Autodesk Fusion 360 part; units mm, degrees
(part 7 of 7)
  spline S31 degree 5 poles (-13.4039, -14.1628) (-13.3959, -14.1604) (-13.3799, -14.1556) (-13.356, -14.1483) (-13.3241, -14.1385) (-13.2844, -14.1261) (-13.2448, -14.1135) (-13.2053, -14.1007) (-13.1659, -14.0879) (-13.1266, -14.0748) (-13.0874, -14.0616) (-13.0484, -14.0482) (-13.0094, -14.0347) (-12.9706, -14.021) (-12.9319, -14.0072) (-12.8933, -13.9932) (-12.8548, -13.979) (-12.8164, -13.9647) (-12.7782, -13.9502) (-12.7401, -13.9355) (-12.7021, -13.9207) (-12.6642, -13.9057) (-12.6265, -13.8905) (-12.5889, -13.8752) (-12.5514, -13.8597) (-12.5141, -13.844) (-12.4768, -13.8282) (-12.4398, -13.8122) (-12.4028, -13.796) (-12.366, -13.7797) (-12.3294, -13.7632) (-12.2928, -13.7465) (-12.2565, -13.7296) (-12.2202, -13.7126) (-12.1842, -13.6954) (-12.1482, -13.678) (-12.1124, -13.6604) (-12.0768, -13.6426) (-12.0413, -13.6247) (-12.006, -13.6066) (-11.9709, -13.5883) (-11.9359, -13.5698) (-11.9011, -13.5511) (-11.8664, -13.5322) (-11.832, -13.5131) (-11.7977, -13.4939) (-11.7636, -13.4744) (-11.7296, -13.4547) (-11.6959, -13.4349) (-11.6623, -13.4148) (-11.6289, -13.3946) (-11.5958, -13.3741) (-11.5628, -13.3533) (-11.5301, -13.3324) (-11.4976, -13.3112) (-11.4653, -13.2898) (-11.4332, -13.2682) (-11.4013, -13.2464) (-11.3696, -13.2244) (-11.3382, -13.2021) (-11.307, -13.1795) (-11.2762, -13.1566) (-11.2458, -13.1334) (-11.2157, -13.1098) (-11.186, -13.0858) (-11.1564, -13.0617) (-11.1271, -13.0374) (-11.098, -13.0129) (-11.0691, -12.9882) (-11.0407, -12.963) (-11.0131, -12.9371) (-10.9919, -12.9156) (-10.9766, -12.8989) (-10.9666, -12.8875) (-10.9617, -12.8818) knots -1 -1 -1 -1 -1 -1 -0.98571429 -0.97142857 -0.95714286 -0.94285714 -0.92857143 -0.91428571 -0.9 -0.88571429 -0.87142857 -0.85714286 -0.84285714 -0.82857143 -0.81428571 -0.8 -0.78571429 -0.77142857 -0.75714286 -0.74285714 -0.72857143 -0.71428571 -0.7 -0.68571429 -0.67142857 -0.65714286 -0.64285714 -0.62857143 -0.61428571 -0.6 -0.58571429 -0.57142857 -0.55714286 -0.54285714 -0.52857143 -0.51428571 -0.5 -0.48571429 -0.47142857 -0.45714286 -0.44285714 -0.42857143 -0.41428571 -0.4 -0.38571429 -0.37142857 -0.35714286 -0.34285714 -0.32857143 -0.31428571 -0.3 -0.28571429 -0.27142857 -0.25714286 -0.24285714 -0.22857143 -0.21428571 -0.2 -0.18571429 -0.17142857 -0.15714286 -0.14285714 -0.12857143 -0.11428571 -0.1 -0.08571429 -0.07142857 -0.05714286 -0.04285714 -0.02857143 -0.01428571 0 0 0 0 0 0
  line L31 (-10.9617, -12.8818) -> (-10.8597, -12.7619)
  arc A63 (-10.1664, -12.6956) -> (-10.8597, -12.7619) centre (-10.4789, -13.0859) ccw
  arc A64 (-10.1664, -12.6956) -> (-9.6318, -13.1058) centre (0, 0) ccw
  arc A65 (-9.5163, -13.7927) -> (-9.6318, -13.1058) centre (-9.9279, -13.5087) ccw
  line L32 (-9.5163, -13.7927) -> (-9.6057, -13.9222)
  spline S32 degree 5 poles (-9.6057, -13.9222) (-9.61, -13.9285) (-9.6185, -13.941) (-9.6306, -13.9602) (-9.6459, -13.9862) (-9.6638, -14.0196) (-9.6807, -14.0535) (-9.6971, -14.0878) (-9.7132, -14.1223) (-9.7291, -14.1569) (-9.7448, -14.1917) (-9.7602, -14.2266) (-9.7752, -14.2618) (-9.7898, -14.2972) (-9.804, -14.3329) (-9.8177, -14.3688) (-9.8311, -14.4049) (-9.8441, -14.4412) (-9.8569, -14.4777) (-9.8695, -14.5143) (-9.8818, -14.551) (-9.8939, -14.5879) (-9.9057, -14.6249) (-9.9171, -14.6621) (-9.9284, -14.6994) (-9.9393, -14.7369) (-9.95, -14.7745) (-9.9604, -14.8123) (-9.9706, -14.8502) (-9.9806, -14.8882) (-9.9903, -14.9263) (-9.9998, -14.9645) (-10.0091, -15.0028) (-10.0182, -15.0413) (-10.027, -15.0799) (-10.0356, -15.1186) (-10.0439, -15.1574) (-10.0521, -15.1963) (-10.06, -15.2353) (-10.0677, -15.2744) (-10.0752, -15.3136) (-10.0825, -15.3529) (-10.0896, -15.3923) (-10.0965, -15.4318) (-10.1031, -15.4714) (-10.1096, -15.5111) (-10.1159, -15.5509) (-10.1219, -15.5908) (-10.1278, -15.6307) (-10.1334, -15.6708) (-10.1389, -15.7109) (-10.1442, -15.7511) (-10.1492, -15.7914) (-10.1541, -15.8318) (-10.1588, -15.8722) (-10.1633, -15.9127) (-10.1676, -15.9533) (-10.1717, -15.994) (-10.1756, -16.0348) (-10.1793, -16.0756) (-10.1829, -16.1165) (-10.1862, -16.1575) (-10.1894, -16.1986) (-10.1924, -16.2397) (-10.1952, -16.2809) (-10.1978, -16.3221) (-10.2002, -16.3635) (-10.2025, -16.4049) (-10.2046, -16.4463) (-10.2065, -16.4878) (-10.2082, -16.5294) (-10.2094, -16.5627) (-10.2102, -16.5878) (-10.2108, -16.6045) (-10.211, -16.6128) knots 0 0 0 0 0 0 0.01428571 0.02857143 0.04285714 0.05714286 0.07142857 0.08571429 0.1 0.11428571 0.12857143 0.14285714 0.15714286 0.17142857 0.18571429 0.2 0.21428571 0.22857143 0.24285714 0.25714286 0.27142857 0.28571429 0.3 0.31428571 0.32857143 0.34285714 0.35714286 0.37142857 0.38571429 0.4 0.41428571 0.42857143 0.44285714 0.45714286 0.47142857 0.48571429 0.5 0.51428571 0.52857143 0.54285714 0.55714286 0.57142857 0.58571429 0.6 0.61428571 0.62857143 0.64285714 0.65714286 0.67142857 0.68571429 0.7 0.71428571 0.72857143 0.74285714 0.75714286 0.77142857 0.78571429 0.8 0.81428571 0.82857143 0.84285714 0.85714286 0.87142857 0.88571429 0.9 0.91428571 0.92857143 0.94285714 0.95714286 0.97142857 0.98571429 1 1 1 1 1 1
  arc A66 (-10.211, -16.6128) -> (-9.2816, -17.1494) centre (0, 0) ccw
  spline S33 degree 5 poles (-9.2816, -17.1494) (-9.2745, -17.145) (-9.2603, -17.1362) (-9.2391, -17.123) (-9.2108, -17.1053) (-9.1757, -17.083) (-9.1406, -17.0606) (-9.1058, -17.0381) (-9.0711, -17.0154) (-9.0365, -16.9926) (-9.0021, -16.9697) (-8.9678, -16.9467) (-8.9337, -16.9236) (-8.8997, -16.9003) (-8.8659, -16.8769) (-8.8322, -16.8534) (-8.7987, -16.8297) (-8.7654, -16.806) (-8.7322, -16.7821) (-8.6992, -16.758) (-8.6663, -16.7339) (-8.6336, -16.7096) (-8.6011, -16.6852) (-8.5688, -16.6606) (-8.5366, -16.636) (-8.5045, -16.6112) (-8.4727, -16.5863) (-8.441, -16.5612) (-8.4095, -16.536) (-8.3782, -16.5107) (-8.3471, -16.4853) (-8.3161, -16.4597) (-8.2853, -16.434) (-8.2548, -16.4082) (-8.2244, -16.3822) (-8.1942, -16.3561) (-8.1642, -16.3299) (-8.1343, -16.3035) (-8.1047, -16.277) (-8.0753, -16.2503) (-8.0461, -16.2236) (-8.0171, -16.1966) (-7.9883, -16.1696) (-7.9597, -16.1424) (-7.9314, -16.115) (-7.9032, -16.0875) (-7.8753, -16.0599) (-7.8476, -16.0321) (-7.8201, -16.0042) (-7.7929, -15.9762) (-7.7659, -15.9479) (-7.7392, -15.9196) (-7.7127, -15.891) (-7.6866, -15.8623) (-7.6606, -15.8334) (-7.635, -15.8044) (-7.6096, -15.7752) (-7.5844, -15.7459) (-7.5595, -15.7164) (-7.5349, -15.6868) (-7.5106, -15.6569) (-7.4868, -15.6268) (-7.4634, -15.5965) (-7.4405, -15.5659) (-7.4179, -15.5351) (-7.3957, -15.5041) (-7.3736, -15.4731) (-7.3518, -15.4419) (-7.3303, -15.4105) (-7.3094, -15.3789) (-7.2895, -15.3467) (-7.2745, -15.3204) (-7.2641, -15.3003) (-7.2574, -15.2868) (-7.2542, -15.2799) knots -1 -1 -1 -1 -1 -1 -0.98571429 -0.97142857 -0.95714286 -0.94285714 -0.92857143 -0.91428571 -0.9 -0.88571429 -0.87142857 -0.85714286 -0.84285714 -0.82857143 -0.81428571 -0.8 -0.78571429 -0.77142857 -0.75714286 -0.74285714 -0.72857143 -0.71428571 -0.7 -0.68571429 -0.67142857 -0.65714286 -0.64285714 -0.62857143 -0.61428571 -0.6 -0.58571429 -0.57142857 -0.55714286 -0.54285714 -0.52857143 -0.51428571 -0.5 -0.48571429 -0.47142857 -0.45714286 -0.44285714 -0.42857143 -0.41428571 -0.4 -0.38571429 -0.37142857 -0.35714286 -0.34285714 -0.32857143 -0.31428571 -0.3 -0.28571429 -0.27142857 -0.25714286 -0.24285714 -0.22857143 -0.21428571 -0.2 -0.18571429 -0.17142857 -0.15714286 -0.14285714 -0.12857143 -0.11428571 -0.1 -0.08571429 -0.07142857 -0.05714286 -0.04285714 -0.02857143 -0.01428571 0 0 0 0 0 0
  line L33 (-7.2542, -15.2799) -> (-7.1866, -15.1377)
  arc A67 (-6.5341, -14.8943) -> (-7.1866, -15.1377) centre (-6.735, -15.3522) ccw
  arc A68 (-6.5341, -14.8943) -> (-5.9116, -15.1521) centre (0, 0) ccw
  arc A69 (-5.6223, -15.7857) -> (-5.9116, -15.1521) centre (-6.0933, -15.6179) ccw
  line L34 (-5.6223, -15.7857) -> (-5.6751, -15.934)
  spline S34 degree 5 poles (-5.6751, -15.934) (-5.6776, -15.9411) (-5.6825, -15.9554) (-5.6893, -15.9771) (-5.6973, -16.0062) (-5.706, -16.043) (-5.7136, -16.0802) (-5.7205, -16.1176) (-5.7271, -16.1551) (-5.7335, -16.1926) (-5.7397, -16.2302) (-5.7455, -16.268) (-5.7509, -16.3058) (-5.7559, -16.3438) (-5.7603, -16.3819) (-5.7643, -16.4202) (-5.7678, -16.4586) (-5.771, -16.497) (-5.774, -16.5355) (-5.7766, -16.5741) (-5.779, -16.6128) (-5.7811, -16.6515) (-5.7829, -16.6904) (-5.7844, -16.7293) (-5.7856, -16.7682) (-5.7864, -16.8073) (-5.787, -16.8464) (-5.7873, -16.8855) (-5.7874, -16.9247) (-5.7872, -16.964) (-5.7867, -17.0034) (-5.786, -17.0427) (-5.785, -17.0822) (-5.7838, -17.1217) (-5.7824, -17.1612) (-5.7806, -17.2008) (-5.7787, -17.2405) (-5.7765, -17.2802) (-5.774, -17.3199) (-5.7714, -17.3597) (-5.7685, -17.3995) (-5.7653, -17.4393) (-5.762, -17.4792) (-5.7584, -17.5192) (-5.7546, -17.5591) (-5.7506, -17.5991) (-5.7463, -17.6392) (-5.7418, -17.6793) (-5.7372, -17.7194) (-5.7323, -17.7595) (-5.7272, -17.7997) (-5.7218, -17.8399) (-5.7163, -17.8801) (-5.7106, -17.9204) (-5.7046, -17.9607) (-5.6985, -18.001) (-5.6921, -18.0413) (-5.6855, -18.0817) (-5.6788, -18.1221) (-5.6718, -18.1625) (-5.6646, -18.2029) (-5.6573, -18.2434) (-5.6497, -18.2838) (-5.6419, -18.3243) (-5.634, -18.3648) (-5.6258, -18.4054) (-5.6175, -18.4459) (-5.609, -18.4865) (-5.6002, -18.5271) (-5.5913, -18.5677) (-5.5822, -18.6083) (-5.5748, -18.6408) (-5.5691, -18.6652) (-5.5653, -18.6814) (-5.5634, -18.6895) knots 0 0 0 0 0 0 0.01428571 0.02857143 0.04285714 0.05714286 0.07142857 0.08571429 0.1 0.11428571 0.12857143 0.14285714 0.15714286 0.17142857 0.18571429 0.2 0.21428571 0.22857143 0.24285714 0.25714286 0.27142857 0.28571429 0.3 0.31428571 0.32857143 0.34285714 0.35714286 0.37142857 0.38571429 0.4 0.41428571 0.42857143 0.44285714 0.45714286 0.47142857 0.48571429 0.5 0.51428571 0.52857143 0.54285714 0.55714286 0.57142857 0.58571429 0.6 0.61428571 0.62857143 0.64285714 0.65714286 0.67142857 0.68571429 0.7 0.71428571 0.72857143 0.74285714 0.75714286 0.77142857 0.78571429 0.8 0.81428571 0.82857143 0.84285714 0.85714286 0.87142857 0.88571429 0.9 0.91428571 0.92857143 0.94285714 0.95714286 0.97142857 0.98571429 1 1 1 1 1 1
  arc A70 (-5.5634, -18.6895) -> (-4.5267, -18.9673) centre (0, 0) ccw
  spline S35 degree 5 poles (-4.5267, -18.9673) (-4.521, -18.9612) (-4.5096, -18.949) (-4.4925, -18.9308) (-4.4698, -18.9063) (-4.4416, -18.8757) (-4.4136, -18.845) (-4.3857, -18.8142) (-4.3581, -18.7834) (-4.3306, -18.7524) (-4.3032, -18.7214) (-4.2761, -18.6903) (-4.2491, -18.6591) (-4.2223, -18.6278) (-4.1957, -18.5965) (-4.1693, -18.5651) (-4.1431, -18.5336) (-4.117, -18.502) (-4.0912, -18.4703) (-4.0655, -18.4385) (-4.04, -18.4067) (-4.0147, -18.3748) (-3.9896, -18.3428) (-3.9647, -18.3107) (-3.94, -18.2786) (-3.9155, -18.2463) (-3.8912, -18.214) (-3.867, -18.1816) (-3.8431, -18.1491) (-3.8194, -18.1166) (-3.7959, -18.0839) (-3.7727, -18.0512) (-3.7496, -18.0184) (-3.7267, -17.9856) (-3.7041, -17.9526) (-3.6817, -17.9196) (-3.6595, -17.8865) (-3.6375, -17.8533) (-3.6158, -17.82) (-3.5942, -17.7867) (-3.573, -17.7532) (-3.5519, -17.7197) (-3.5311, -17.6861) (-3.5105, -17.6525) (-3.4902, -17.6187) (-3.4702, -17.5849) (-3.4504, -17.551) (-3.4308, -17.517) (-3.4115, -17.4829) (-3.3924, -17.4487) (-3.3737, -17.4145) (-3.3552, -17.3802) (-3.337, -17.3457) (-3.3192, -17.3112) (-3.3016, -17.2766) (-3.2844, -17.2419) (-3.2674, -17.2072) (-3.2506, -17.1724) (-3.2342, -17.1374) (-3.2181, -17.1024) (-3.2024, -17.0673) (-3.1872, -17.0321) (-3.1724, -16.9967) (-3.1582, -16.9612) (-3.1444, -16.9257) (-3.1309, -16.89) (-3.1177, -16.8543) (-3.1047, -16.8185) (-3.092, -16.7827) (-3.08, -16.7467) (-3.0691, -16.7104) (-3.0614, -16.6812) (-3.0565, -16.6591) (-3.0536, -16.6442) (-3.0522, -16.6368) knots -1 -1 -1 -1 -1 -1 -0.98571429 -0.97142857 -0.95714286 -0.94285714 -0.92857143 -0.91428571 -0.9 -0.88571429 -0.87142857 -0.85714286 -0.84285714 -0.82857143 -0.81428571 -0.8 -0.78571429 -0.77142857 -0.75714286 -0.74285714 -0.72857143 -0.71428571 -0.7 -0.68571429 -0.67142857 -0.65714286 -0.64285714 -0.62857143 -0.61428571 -0.6 -0.58571429 -0.57142857 -0.55714286 -0.54285714 -0.52857143 -0.51428571 -0.5 -0.48571429 -0.47142857 -0.45714286 -0.44285714 -0.42857143 -0.41428571 -0.4 -0.38571429 -0.37142857 -0.35714286 -0.34285714 -0.32857143 -0.31428571 -0.3 -0.28571429 -0.27142857 -0.25714286 -0.24285714 -0.22857143 -0.21428571 -0.2 -0.18571429 -0.17142857 -0.15714286 -0.14285714 -0.12857143 -0.11428571 -0.1 -0.08571429 -0.07142857 -0.05714286 -0.04285714 -0.02857143 -0.01428571 0 0 0 0 0 0
  line L35 (-3.0522, -16.6368) -> (-3.0238, -16.482)
  arc A71 (-2.4565, -16.0779) -> (-3.0238, -16.482) centre (-2.532, -16.5722) ccw
  arc A72 (-2.4565, -16.0779) -> (-1.7885, -16.1659) centre (0, 0) ccw
  arc A73 (-1.3451, -16.703) -> (-1.7885, -16.1659) centre (-1.8434, -16.6628) ccw
  line L36 (-1.3451, -16.703) -> (-1.3577, -16.8599)
  spline S36 degree 5 poles (-1.3577, -16.8599) (-1.3583, -16.8674) (-1.3593, -16.8825) (-1.3603, -16.9052) (-1.3605, -16.9354) (-1.3593, -16.9732) (-1.357, -17.0111) (-1.3541, -17.049) (-1.3508, -17.0869) (-1.3472, -17.1248) (-1.3434, -17.1628) (-1.3393, -17.2007) (-1.3347, -17.2387) (-1.3297, -17.2766) (-1.3241, -17.3146) (-1.318, -17.3526) (-1.3115, -17.3906) (-1.3047, -17.4285) (-1.2975, -17.4665) (-1.2901, -17.5045) (-1.2824, -17.5425) (-1.2744, -17.5804) (-1.2661, -17.6184) (-1.2574, -17.6563) (-1.2485, -17.6943) (-1.2392, -17.7322) (-1.2297, -17.7701) (-1.2198, -17.808) (-1.2097, -17.8459) (-1.1994, -17.8838) (-1.1888, -17.9217) (-1.1779, -17.9596) (-1.1667, -17.9974) (-1.1553, -18.0352) (-1.1437, -18.0731) (-1.1318, -18.1109) (-1.1196, -18.1486) (-1.1072, -18.1864) (-1.0946, -18.2242) (-1.0817, -18.2619) (-1.0686, -18.2996) (-1.0553, -18.3373) (-1.0417, -18.3749) (-1.0279, -18.4126) (-1.0139, -18.4502) (-0.9996, -18.4878) (-0.9852, -18.5254) (-0.9705, -18.563) (-0.9556, -18.6005) (-0.9404, -18.638) (-0.9251, -18.6755) (-0.9096, -18.7129) (-0.8938, -18.7504) (-0.8778, -18.7878) (-0.8617, -18.8251) (-0.8453, -18.8625) (-0.8287, -18.8998) (-0.8119, -18.9371) (-0.7949, -18.9743) (-0.7777, -19.0116) (-0.7604, -19.0488) (-0.7428, -19.0859) (-0.725, -19.1231) (-0.707, -19.1602) (-0.6888, -19.1973) (-0.6705, -19.2343) (-0.6519, -19.2713) (-0.6332, -19.3083) (-0.6143, -19.3452) (-0.5951, -19.3821) (-0.5758, -19.419) (-0.5602, -19.4485) (-0.5484, -19.4705) (-0.5406, -19.4853) (-0.5366, -19.4926) knots 0 0 0 0 0 0 0.01428571 0.02857143 0.04285714 0.05714286 0.07142857 0.08571429 0.1 0.11428571 0.12857143 0.14285714 0.15714286 0.17142857 0.18571429 0.2 0.21428571 0.22857143 0.24285714 0.25714286 0.27142857 0.28571429 0.3 0.31428571 0.32857143 0.34285714 0.35714286 0.37142857 0.38571429 0.4 0.41428571 0.42857143 0.44285714 0.45714286 0.47142857 0.48571429 0.5 0.51428571 0.52857143 0.54285714 0.55714286 0.57142857 0.58571429 0.6 0.61428571 0.62857143 0.64285714 0.65714286 0.67142857 0.68571429 0.7 0.71428571 0.72857143 0.74285714 0.75714286 0.77142857 0.78571429 0.8 0.81428571 0.82857143 0.84285714 0.85714286 0.87142857 0.88571429 0.9 0.91428571 0.92857143 0.94285714 0.95714286 0.97142857 0.98571429 1 1 1 1 1 1
  arc A74 (-0.5366, -19.4926) -> (0.5366, -19.4926) centre (0, 0) ccw
  spline S37 degree 5 poles (0.5366, -19.4926) (0.5406, -19.4853) (0.5484, -19.4705) (0.5602, -19.4485) (0.5758, -19.419) (0.5951, -19.3821) (0.6143, -19.3452) (0.6332, -19.3083) (0.6519, -19.2713) (0.6705, -19.2343) (0.6888, -19.1973) (0.707, -19.1602) (0.725, -19.1231) (0.7428, -19.0859) (0.7604, -19.0488) (0.7777, -19.0116) (0.7949, -18.9743) (0.8119, -18.9371) (0.8287, -18.8998) (0.8453, -18.8625) (0.8617, -18.8251) (0.8778, -18.7878) (0.8938, -18.7504) (0.9096, -18.7129) (0.9251, -18.6755) (0.9404, -18.638) (0.9556, -18.6005) (0.9705, -18.563) (0.9852, -18.5254) (0.9996, -18.4878) (1.0139, -18.4502) (1.0279, -18.4126) (1.0417, -18.3749) (1.0553, -18.3373) (1.0686, -18.2996) (1.0817, -18.2619) (1.0946, -18.2242) (1.1072, -18.1864) (1.1196, -18.1486) (1.1318, -18.1109) (1.1437, -18.0731) (1.1553, -18.0352) (1.1667, -17.9974) (1.1779, -17.9596) (1.1888, -17.9217) (1.1994, -17.8838) (1.2097, -17.8459) (1.2198, -17.808) (1.2297, -17.7701) (1.2392, -17.7322) (1.2485, -17.6943) (1.2574, -17.6563) (1.2661, -17.6184) (1.2744, -17.5804) (1.2824, -17.5425) (1.2901, -17.5045) (1.2975, -17.4665) (1.3047, -17.4285) (1.3115, -17.3906) (1.318, -17.3526) (1.3241, -17.3146) (1.3297, -17.2766) (1.3347, -17.2387) (1.3393, -17.2007) (1.3434, -17.1628) (1.3472, -17.1248) (1.3508, -17.0869) (1.3541, -17.049) (1.357, -17.0111) (1.3593, -16.9732) (1.3605, -16.9354) (1.3603, -16.9052) (1.3593, -16.8825) (1.3583, -16.8674) (1.3577, -16.8599) knots -1 -1 -1 -1 -1 -1 -0.98571429 -0.97142857 -0.95714286 -0.94285714 -0.92857143 -0.91428571 -0.9 -0.88571429 -0.87142857 -0.85714286 -0.84285714 -0.82857143 -0.81428571 -0.8 -0.78571429 -0.77142857 -0.75714286 -0.74285714 -0.72857143 -0.71428571 -0.7 -0.68571429 -0.67142857 -0.65714286 -0.64285714 -0.62857143 -0.61428571 -0.6 -0.58571429 -0.57142857 -0.55714286 -0.54285714 -0.52857143 -0.51428571 -0.5 -0.48571429 -0.47142857 -0.45714286 -0.44285714 -0.42857143 -0.41428571 -0.4 -0.38571429 -0.37142857 -0.35714286 -0.34285714 -0.32857143 -0.31428571 -0.3 -0.28571429 -0.27142857 -0.25714286 -0.24285714 -0.22857143 -0.21428571 -0.2 -0.18571429 -0.17142857 -0.15714286 -0.14285714 -0.12857143 -0.11428571 -0.1 -0.08571429 -0.07142857 -0.05714286 -0.04285714 -0.02857143 -0.01428571 0 0 0 0 0 0
  line L37 (1.3577, -16.8599) -> (1.3451, -16.703)
  arc A75 (1.7885, -16.1659) -> (1.3451, -16.703) centre (1.8434, -16.6628) ccw
  arc A76 (1.7885, -16.1659) -> (2.4565, -16.0779) centre (0, 0) ccw
  arc A77 (3.0238, -16.482) -> (2.4565, -16.0779) centre (2.532, -16.5722) ccw
  line L38 (3.0238, -16.482) -> (3.0522, -16.6368)
  spline S38 degree 5 poles (3.0522, -16.6368) (3.0536, -16.6442) (3.0565, -16.6591) (3.0614, -16.6812) (3.0691, -16.7104) (3.08, -16.7467) (3.092, -16.7827) (3.1047, -16.8185) (3.1177, -16.8543) (3.1309, -16.89) (3.1444, -16.9257) (3.1582, -16.9612) (3.1724, -16.9967) (3.1872, -17.0321) (3.2024, -17.0673) (3.2181, -17.1024) (3.2342, -17.1374) (3.2506, -17.1724) (3.2674, -17.2072) (3.2844, -17.2419) (3.3016, -17.2766) (3.3192, -17.3112) (3.337, -17.3457) (3.3552, -17.3802) (3.3737, -17.4145) (3.3924, -17.4487) (3.4115, -17.4829) (3.4308, -17.517) (3.4504, -17.551) (3.4702, -17.5849) (3.4902, -17.6187) (3.5105, -17.6525) (3.5311, -17.6861) (3.5519, -17.7197) (3.573, -17.7532) (3.5942, -17.7867) (3.6158, -17.82) (3.6375, -17.8533) (3.6595, -17.8865) (3.6817, -17.9196) (3.7041, -17.9526) (3.7267, -17.9856) (3.7496, -18.0184) (3.7727, -18.0512) (3.7959, -18.0839) (3.8194, -18.1166) (3.8431, -18.1491) (3.867, -18.1816) (3.8912, -18.214) (3.9155, -18.2463) (3.94, -18.2786) (3.9647, -18.3107) (3.9896, -18.3428) (4.0147, -18.3748) (4.04, -18.4067) (4.0655, -18.4385) (4.0912, -18.4703) (4.117, -18.502) (4.1431, -18.5336) (4.1693, -18.5651) (4.1957, -18.5965) (4.2223, -18.6278) (4.2491, -18.6591) (4.2761, -18.6903) (4.3032, -18.7214) (4.3306, -18.7524) (4.3581, -18.7834) (4.3857, -18.8142) (4.4136, -18.845) (4.4416, -18.8757) (4.4698, -18.9063) (4.4925, -18.9308) (4.5096, -18.949) (4.521, -18.9612) (4.5267, -18.9673) knots 0 0 0 0 0 0 0.01428571 0.02857143 0.04285714 0.05714286 0.07142857 0.08571429 0.1 0.11428571 0.12857143 0.14285714 0.15714286 0.17142857 0.18571429 0.2 0.21428571 0.22857143 0.24285714 0.25714286 0.27142857 0.28571429 0.3 0.31428571 0.32857143 0.34285714 0.35714286 0.37142857 0.38571429 0.4 0.41428571 0.42857143 0.44285714 0.45714286 0.47142857 0.48571429 0.5 0.51428571 0.52857143 0.54285714 0.55714286 0.57142857 0.58571429 0.6 0.61428571 0.62857143 0.64285714 0.65714286 0.67142857 0.68571429 0.7 0.71428571 0.72857143 0.74285714 0.75714286 0.77142857 0.78571429 0.8 0.81428571 0.82857143 0.84285714 0.85714286 0.87142857 0.88571429 0.9 0.91428571 0.92857143 0.94285714 0.95714286 0.97142857 0.98571429 1 1 1 1 1 1
  arc A78 (4.5267, -18.9673) -> (5.5634, -18.6895) centre (0, 0) ccw
  spline S39 degree 5 poles (5.5634, -18.6895) (5.5653, -18.6814) (5.5691, -18.6652) (5.5748, -18.6408) (5.5822, -18.6083) (5.5913, -18.5677) (5.6002, -18.5271) (5.609, -18.4865) (5.6175, -18.4459) (5.6258, -18.4054) (5.634, -18.3648) (5.6419, -18.3243) (5.6497, -18.2838) (5.6573, -18.2434) (5.6646, -18.2029) (5.6718, -18.1625) (5.6788, -18.1221) (5.6855, -18.0817) (5.6921, -18.0413) (5.6985, -18.001) (5.7046, -17.9607) (5.7106, -17.9204) (5.7163, -17.8801) (5.7218, -17.8399) (5.7272, -17.7997) (5.7323, -17.7595) (5.7372, -17.7194) (5.7418, -17.6793) (5.7463, -17.6392) (5.7506, -17.5991) (5.7546, -17.5591) (5.7584, -17.5192) (5.762, -17.4792) (5.7653, -17.4393) (5.7685, -17.3995) (5.7714, -17.3597) (5.774, -17.3199) (5.7765, -17.2802) (5.7787, -17.2405) (5.7806, -17.2008) (5.7824, -17.1612) (5.7838, -17.1217) (5.785, -17.0822) (5.786, -17.0427) (5.7867, -17.0034) (5.7872, -16.964) (5.7874, -16.9247) (5.7873, -16.8855) (5.787, -16.8464) (5.7864, -16.8073) (5.7856, -16.7682) (5.7844, -16.7293) (5.7829, -16.6904) (5.7811, -16.6515) (5.779, -16.6128) (5.7766, -16.5741) (5.774, -16.5355) (5.771, -16.497) (5.7678, -16.4586) (5.7643, -16.4202) (5.7603, -16.3819) (5.7559, -16.3438) (5.7509, -16.3058) (5.7455, -16.268) (5.7397, -16.2302) (5.7335, -16.1926) (5.7271, -16.1551) (5.7205, -16.1176) (5.7136, -16.0802) (5.706, -16.043) (5.6973, -16.0062) (5.6893, -15.9771) (5.6825, -15.9554) (5.6776, -15.9411) (5.6751, -15.934) knots -1 -1 -1 -1 -1 -1 -0.98571429 -0.97142857 -0.95714286 -0.94285714 -0.92857143 -0.91428571 -0.9 -0.88571429 -0.87142857 -0.85714286 -0.84285714 -0.82857143 -0.81428571 -0.8 -0.78571429 -0.77142857 -0.75714286 -0.74285714 -0.72857143 -0.71428571 -0.7 -0.68571429 -0.67142857 -0.65714286 -0.64285714 -0.62857143 -0.61428571 -0.6 -0.58571429 -0.57142857 -0.55714286 -0.54285714 -0.52857143 -0.51428571 -0.5 -0.48571429 -0.47142857 -0.45714286 -0.44285714 -0.42857143 -0.41428571 -0.4 -0.38571429 -0.37142857 -0.35714286 -0.34285714 -0.32857143 -0.31428571 -0.3 -0.28571429 -0.27142857 -0.25714286 -0.24285714 -0.22857143 -0.21428571 -0.2 -0.18571429 -0.17142857 -0.15714286 -0.14285714 -0.12857143 -0.11428571 -0.1 -0.08571429 -0.07142857 -0.05714286 -0.04285714 -0.02857143 -0.01428571 0 0 0 0 0 0
  line L39 (5.6751, -15.934) -> (5.6223, -15.7857)
  arc A79 (5.9116, -15.1521) -> (5.6223, -15.7857) centre (6.0933, -15.6179) ccw
  arc A80 (5.9116, -15.1521) -> (6.5341, -14.8943) centre (0, 0) ccw
  arc A81 (7.1866, -15.1377) -> (6.5341, -14.8943) centre (6.735, -15.3522) ccw
  line L40 (7.1866, -15.1377) -> (7.2542, -15.2799)
  spline S40 degree 5 poles (7.2542, -15.2799) (7.2574, -15.2868) (7.2641, -15.3003) (7.2745, -15.3204) (7.2895, -15.3467) (7.3094, -15.3789) (7.3303, -15.4105) (7.3518, -15.4419) (7.3736, -15.4731) (7.3957, -15.5041) (7.4179, -15.5351) (7.4405, -15.5659) (7.4634, -15.5965) (7.4868, -15.6268) (7.5106, -15.6569) (7.5349, -15.6868) (7.5595, -15.7164) (7.5844, -15.7459) (7.6096, -15.7752) (7.635, -15.8044) (7.6606, -15.8334) (7.6866, -15.8623) (7.7127, -15.891) (7.7392, -15.9196) (7.7659, -15.9479) (7.7929, -15.9762) (7.8201, -16.0042) (7.8476, -16.0321) (7.8753, -16.0599) (7.9032, -16.0875) (7.9314, -16.115) (7.9597, -16.1424) (7.9883, -16.1696) (8.0171, -16.1966) (8.0461, -16.2236) (8.0753, -16.2503) (8.1047, -16.277) (8.1343, -16.3035) (8.1642, -16.3299) (8.1942, -16.3561) (8.2244, -16.3822) (8.2548, -16.4082) (8.2853, -16.434) (8.3161, -16.4597) (8.3471, -16.4853) (8.3782, -16.5107) (8.4095, -16.536) (8.441, -16.5612) (8.4727, -16.5863) (8.5045, -16.6112) (8.5366, -16.636) (8.5688, -16.6606) (8.6011, -16.6852) (8.6336, -16.7096) (8.6663, -16.7339) (8.6992, -16.758) (8.7322, -16.7821) (8.7654, -16.806) (8.7987, -16.8297) (8.8322, -16.8534) (8.8659, -16.8769) (8.8997, -16.9003) (8.9337, -16.9236) (8.9678, -16.9467) (9.0021, -16.9697) (9.0365, -16.9926) (9.0711, -17.0154) (9.1058, -17.0381) (9.1406, -17.0606) (9.1757, -17.083) (9.2108, -17.1053) (9.2391, -17.123) (9.2603, -17.1362) (9.2745, -17.145) (9.2816, -17.1494) knots 0 0 0 0 0 0 0.01428571 0.02857143 0.04285714 0.05714286 0.07142857 0.08571429 0.1 0.11428571 0.12857143 0.14285714 0.15714286 0.17142857 0.18571429 0.2 0.21428571 0.22857143 0.24285714 0.25714286 0.27142857 0.28571429 0.3 0.31428571 0.32857143 0.34285714 0.35714286 0.37142857 0.38571429 0.4 0.41428571 0.42857143 0.44285714 0.45714286 0.47142857 0.48571429 0.5 0.51428571 0.52857143 0.54285714 0.55714286 0.57142857 0.58571429 0.6 0.61428571 0.62857143 0.64285714 0.65714286 0.67142857 0.68571429 0.7 0.71428571 0.72857143 0.74285714 0.75714286 0.77142857 0.78571429 0.8 0.81428571 0.82857143 0.84285714 0.85714286 0.87142857 0.88571429 0.9 0.91428571 0.92857143 0.94285714 0.95714286 0.97142857 0.98571429 1 1 1 1 1 1
  arc A82 (9.2816, -17.1494) -> (10.211, -16.6128) centre (0, 0) ccw
  spline S41 degree 5 poles (10.211, -16.6128) (10.2108, -16.6045) (10.2102, -16.5878) (10.2094, -16.5627) (10.2082, -16.5294) (10.2065, -16.4878) (10.2046, -16.4463) (10.2025, -16.4049) (10.2002, -16.3635) (10.1978, -16.3221) (10.1952, -16.2809) (10.1924, -16.2397) (10.1894, -16.1986) (10.1862, -16.1575) (10.1829, -16.1165) (10.1793, -16.0756) (10.1756, -16.0348) (10.1717, -15.994) (10.1676, -15.9533) (10.1633, -15.9127) (10.1588, -15.8722) (10.1541, -15.8318) (10.1492, -15.7914) (10.1442, -15.7511) (10.1389, -15.7109) (10.1334, -15.6708) (10.1278, -15.6307) (10.1219, -15.5908) (10.1159, -15.5509) (10.1096, -15.5111) (10.1031, -15.4714) (10.0965, -15.4318) (10.0896, -15.3923) (10.0825, -15.3529) (10.0752, -15.3136) (10.0677, -15.2744) (10.06, -15.2353) (10.0521, -15.1963) (10.0439, -15.1574) (10.0356, -15.1186) (10.027, -15.0799) (10.0182, -15.0413) (10.0091, -15.0028) (9.9998, -14.9645) (9.9903, -14.9263) (9.9806, -14.8882) (9.9706, -14.8502) (9.9604, -14.8123) (9.95, -14.7745) (9.9393, -14.7369) (9.9284, -14.6994) (9.9171, -14.6621) (9.9057, -14.6249) (9.8939, -14.5879) (9.8818, -14.551) (9.8695, -14.5143) (9.8569, -14.4777) (9.8441, -14.4412) (9.8311, -14.4049) (9.8177, -14.3688) (9.804, -14.3329) (9.7898, -14.2972) (9.7752, -14.2618) (9.7602, -14.2266) (9.7448, -14.1917) (9.7291, -14.1569) (9.7132, -14.1223) (9.6971, -14.0878) (9.6807, -14.0535) (9.6638, -14.0196) (9.6459, -13.9862) (9.6306, -13.9602) (9.6185, -13.941) (9.61, -13.9285) (9.6057, -13.9222) knots -1 -1 -1 -1 -1 -1 -0.98571429 -0.97142857 -0.95714286 -0.94285714 -0.92857143 -0.91428571 -0.9 -0.88571429 -0.87142857 -0.85714286 -0.84285714 -0.82857143 -0.81428571 -0.8 -0.78571429 -0.77142857 -0.75714286 -0.74285714 -0.72857143 -0.71428571 -0.7 -0.68571429 -0.67142857 -0.65714286 -0.64285714 -0.62857143 -0.61428571 -0.6 -0.58571429 -0.57142857 -0.55714286 -0.54285714 -0.52857143 -0.51428571 -0.5 -0.48571429 -0.47142857 -0.45714286 -0.44285714 -0.42857143 -0.41428571 -0.4 -0.38571429 -0.37142857 -0.35714286 -0.34285714 -0.32857143 -0.31428571 -0.3 -0.28571429 -0.27142857 -0.25714286 -0.24285714 -0.22857143 -0.21428571 -0.2 -0.18571429 -0.17142857 -0.15714286 -0.14285714 -0.12857143 -0.11428571 -0.1 -0.08571429 -0.07142857 -0.05714286 -0.04285714 -0.02857143 -0.01428571 0 0 0 0 0 0
  line L41 (9.6057, -13.9222) -> (9.5163, -13.7927)
  arc A83 (9.6318, -13.1058) -> (9.5163, -13.7927) centre (9.9279, -13.5087) ccw
  arc A84 (9.6318, -13.1058) -> (10.1664, -12.6956) centre (0, 0) ccw
  arc A85 (10.8597, -12.7619) -> (10.1664, -12.6956) centre (10.4789, -13.0859) ccw
  line L42 (10.8597, -12.7619) -> (10.9617, -12.8818)
  spline S42 degree 5 poles (10.9617, -12.8818) (10.9666, -12.8875) (10.9766, -12.8989) (10.9919, -12.9156) (11.0131, -12.9371) (11.0407, -12.963) (11.0691, -12.9882) (11.098, -13.0129) (11.1271, -13.0374) (11.1564, -13.0617) (11.186, -13.0858) (11.2157, -13.1098) (11.2458, -13.1334) (11.2762, -13.1566) (11.307, -13.1795) (11.3382, -13.2021) (11.3696, -13.2244) (11.4013, -13.2464) (11.4332, -13.2682) (11.4653, -13.2898) (11.4976, -13.3112) (11.5301, -13.3324) (11.5628, -13.3533) (11.5958, -13.3741) (11.6289, -13.3946) (11.6623, -13.4148) (11.6959, -13.4349) (11.7296, -13.4547) (11.7636, -13.4744) (11.7977, -13.4939) (11.832, -13.5131) (11.8664, -13.5322) (11.9011, -13.5511) (11.9359, -13.5698) (11.9709, -13.5883) (12.006, -13.6066) (12.0413, -13.6247) (12.0768, -13.6426) (12.1124, -13.6604) (12.1482, -13.678) (12.1842, -13.6954) (12.2202, -13.7126) (12.2565, -13.7296) (12.2928, -13.7465) (12.3294, -13.7632) (12.366, -13.7797) (12.4028, -13.796) (12.4398, -13.8122) (12.4768, -13.8282) (12.5141, -13.844) (12.5514, -13.8597) (12.5889, -13.8752) (12.6265, -13.8905) (12.6642, -13.9057) (12.7021, -13.9207) (12.7401, -13.9355) (12.7782, -13.9502) (12.8164, -13.9647) (12.8548, -13.979) (12.8933, -13.9932) (12.9319, -14.0072) (12.9706, -14.021) (13.0094, -14.0347) (13.0484, -14.0482) (13.0874, -14.0616) (13.1266, -14.0748) (13.1659, -14.0879) (13.2053, -14.1007) (13.2448, -14.1135) (13.2844, -14.1261) (13.3241, -14.1385) (13.356, -14.1483) (13.3799, -14.1556) (13.3959, -14.1604) (13.4039, -14.1628) knots 0 0 0 0 0 0 0.01428571 0.02857143 0.04285714 0.05714286 0.07142857 0.08571429 0.1 0.11428571 0.12857143 0.14285714 0.15714286 0.17142857 0.18571429 0.2 0.21428571 0.22857143 0.24285714 0.25714286 0.27142857 0.28571429 0.3 0.31428571 0.32857143 0.34285714 0.35714286 0.37142857 0.38571429 0.4 0.41428571 0.42857143 0.44285714 0.45714286 0.47142857 0.48571429 0.5 0.51428571 0.52857143 0.54285714 0.55714286 0.57142857 0.58571429 0.6 0.61428571 0.62857143 0.64285714 0.65714286 0.67142857 0.68571429 0.7 0.71428571 0.72857143 0.74285714 0.75714286 0.77142857 0.78571429 0.8 0.81428571 0.82857143 0.84285714 0.85714286 0.87142857 0.88571429 0.9 0.91428571 0.92857143 0.94285714 0.95714286 0.97142857 0.98571429 1 1 1 1 1 1
  arc A86 (13.4039, -14.1628) -> (14.1628, -13.4039) centre (0, 0) ccw
  spline S43 degree 5 poles (14.1628, -13.4039) (14.1604, -13.3959) (14.1556, -13.3799) (14.1483, -13.356) (14.1385, -13.3241) (14.1261, -13.2844) (14.1135, -13.2448) (14.1007, -13.2053) (14.0879, -13.1659) (14.0748, -13.1266) (14.0616, -13.0874) (14.0482, -13.0484) (14.0347, -13.0094) (14.021, -12.9706) (14.0072, -12.9319) (13.9932, -12.8933) (13.979, -12.8548) (13.9647, -12.8164) (13.9502, -12.7782) (13.9355, -12.7401) (13.9207, -12.7021) (13.9057, -12.6642) (13.8905, -12.6265) (13.8752, -12.5889) (13.8597, -12.5514) (13.844, -12.5141) (13.8282, -12.4768) (13.8122, -12.4398) (13.796, -12.4028) (13.7797, -12.366) (13.7632, -12.3294) (13.7465, -12.2928) (13.7296, -12.2565) (13.7126, -12.2202) (13.6954, -12.1842) (13.678, -12.1482) (13.6604, -12.1124) (13.6426, -12.0768) (13.6247, -12.0413) (13.6066, -12.006) (13.5883, -11.9709) (13.5698, -11.9359) (13.5511, -11.9011) (13.5322, -11.8664) (13.5131, -11.832) (13.4939, -11.7977) (13.4744, -11.7636) (13.4547, -11.7296) (13.4349, -11.6959) (13.4148, -11.6623) (13.3946, -11.6289) (13.3741, -11.5958) (13.3533, -11.5628) (13.3324, -11.5301) (13.3112, -11.4976) (13.2898, -11.4653) (13.2682, -11.4332) (13.2464, -11.4013) (13.2244, -11.3696) (13.2021, -11.3382) (13.1795, -11.307) (13.1566, -11.2762) (13.1334, -11.2458) (13.1098, -11.2157) (13.0858, -11.186) (13.0617, -11.1564) (13.0374, -11.1271) (13.0129, -11.098) (12.9882, -11.0691) (12.963, -11.0407) (12.9371, -11.0131) (12.9156, -10.9919) (12.8989, -10.9766) (12.8875, -10.9666) (12.8818, -10.9617) knots -1 -1 -1 -1 -1 -1 -0.98571429 -0.97142857 -0.95714286 -0.94285714 -0.92857143 -0.91428571 -0.9 -0.88571429 -0.87142857 -0.85714286 -0.84285714 -0.82857143 -0.81428571 -0.8 -0.78571429 -0.77142857 -0.75714286 -0.74285714 -0.72857143 -0.71428571 -0.7 -0.68571429 -0.67142857 -0.65714286 -0.64285714 -0.62857143 -0.61428571 -0.6 -0.58571429 -0.57142857 -0.55714286 -0.54285714 -0.52857143 -0.51428571 -0.5 -0.48571429 -0.47142857 -0.45714286 -0.44285714 -0.42857143 -0.41428571 -0.4 -0.38571429 -0.37142857 -0.35714286 -0.34285714 -0.32857143 -0.31428571 -0.3 -0.28571429 -0.27142857 -0.25714286 -0.24285714 -0.22857143 -0.21428571 -0.2 -0.18571429 -0.17142857 -0.15714286 -0.14285714 -0.12857143 -0.11428571 -0.1 -0.08571429 -0.07142857 -0.05714286 -0.04285714 -0.02857143 -0.01428571 0 0 0 0 0 0
  line L43 (12.8818, -10.9617) -> (12.7619, -10.8597)
  arc A87 (12.6956, -10.1664) -> (12.7619, -10.8597) centre (13.0859, -10.4789) ccw
  arc A88 (12.6956, -10.1664) -> (13.1058, -9.6318) centre (0, 0) ccw
  arc A89 (13.7927, -9.5163) -> (13.1058, -9.6318) centre (13.5087, -9.9279) ccw
  line L44 (13.7927, -9.5163) -> (13.9222, -9.6057)
  spline S44 degree 5 poles (13.9222, -9.6057) (13.9285, -9.61) (13.941, -9.6185) (13.9602, -9.6306) (13.9862, -9.6459) (14.0196, -9.6638) (14.0535, -9.6807) (14.0878, -9.6971) (14.1223, -9.7132) (14.1569, -9.7291) (14.1917, -9.7448) (14.2266, -9.7602) (14.2618, -9.7752) (14.2972, -9.7898) (14.3329, -9.804) (14.3688, -9.8177) (14.4049, -9.8311) (14.4412, -9.8441) (14.4777, -9.8569) (14.5143, -9.8695) (14.551, -9.8818) (14.5879, -9.8939) (14.6249, -9.9057) (14.6621, -9.9171) (14.6994, -9.9284) (14.7369, -9.9393) (14.7745, -9.95) (14.8123, -9.9604) (14.8502, -9.9706) (14.8882, -9.9806) (14.9263, -9.9903) (14.9645, -9.9998) (15.0028, -10.0091) (15.0413, -10.0182) (15.0799, -10.027) (15.1186, -10.0356) (15.1574, -10.0439) (15.1963, -10.0521) (15.2353, -10.06) (15.2744, -10.0677) (15.3136, -10.0752) (15.3529, -10.0825) (15.3923, -10.0896) (15.4318, -10.0965) (15.4714, -10.1031) (15.5111, -10.1096) (15.5509, -10.1159) (15.5908, -10.1219) (15.6307, -10.1278) (15.6708, -10.1334) (15.7109, -10.1389) (15.7511, -10.1442) (15.7914, -10.1492) (15.8318, -10.1541) (15.8722, -10.1588) (15.9127, -10.1633) (15.9533, -10.1676) (15.994, -10.1717) (16.0348, -10.1756) (16.0756, -10.1793) (16.1165, -10.1829) (16.1575, -10.1862) (16.1986, -10.1894) (16.2397, -10.1924) (16.2809, -10.1952) (16.3221, -10.1978) (16.3635, -10.2002) (16.4049, -10.2025) (16.4463, -10.2046) (16.4878, -10.2065) (16.5294, -10.2082) (16.5627, -10.2094) (16.5878, -10.2102) (16.6045, -10.2108) (16.6128, -10.211) knots 0 0 0 0 0 0 0.01428571 0.02857143 0.04285714 0.05714286 0.07142857 0.08571429 0.1 0.11428571 0.12857143 0.14285714 0.15714286 0.17142857 0.18571429 0.2 0.21428571 0.22857143 0.24285714 0.25714286 0.27142857 0.28571429 0.3 0.31428571 0.32857143 0.34285714 0.35714286 0.37142857 0.38571429 0.4 0.41428571 0.42857143 0.44285714 0.45714286 0.47142857 0.48571429 0.5 0.51428571 0.52857143 0.54285714 0.55714286 0.57142857 0.58571429 0.6 0.61428571 0.62857143 0.64285714 0.65714286 0.67142857 0.68571429 0.7 0.71428571 0.72857143 0.74285714 0.75714286 0.77142857 0.78571429 0.8 0.81428571 0.82857143 0.84285714 0.85714286 0.87142857 0.88571429 0.9 0.91428571 0.92857143 0.94285714 0.95714286 0.97142857 0.98571429 1 1 1 1 1 1
  arc A90 (16.6128, -10.211) -> (17.1494, -9.2816) centre (0, 0) ccw
  spline S45 degree 5 poles (17.1494, -9.2816) (17.145, -9.2745) (17.1362, -9.2603) (17.123, -9.2391) (17.1053, -9.2108) (17.083, -9.1757) (17.0606, -9.1406) (17.0381, -9.1058) (17.0154, -9.0711) (16.9926, -9.0365) (16.9697, -9.0021) (16.9467, -8.9678) (16.9236, -8.9337) (16.9003, -8.8997) (16.8769, -8.8659) (16.8534, -8.8322) (16.8297, -8.7987) (16.806, -8.7654) (16.7821, -8.7322) (16.758, -8.6992) (16.7339, -8.6663) (16.7096, -8.6336) (16.6852, -8.6011) (16.6606, -8.5688) (16.636, -8.5366) (16.6112, -8.5045) (16.5863, -8.4727) (16.5612, -8.441) (16.536, -8.4095) (16.5107, -8.3782) (16.4853, -8.3471) (16.4597, -8.3161) (16.434, -8.2853) (16.4082, -8.2548) (16.3822, -8.2244) (16.3561, -8.1942) (16.3299, -8.1642) (16.3035, -8.1343) (16.277, -8.1047) (16.2503, -8.0753) (16.2236, -8.0461) (16.1966, -8.0171) (16.1696, -7.9883) (16.1424, -7.9597) (16.115, -7.9314) (16.0875, -7.9032) (16.0599, -7.8753) (16.0321, -7.8476) (16.0042, -7.8201) (15.9762, -7.7929) (15.9479, -7.7659) (15.9196, -7.7392) (15.891, -7.7127) (15.8623, -7.6866) (15.8334, -7.6606) (15.8044, -7.635) (15.7752, -7.6096) (15.7459, -7.5844) (15.7164, -7.5595) (15.6868, -7.5349) (15.6569, -7.5106) (15.6268, -7.4868) (15.5965, -7.4634) (15.5659, -7.4405) (15.5351, -7.4179) (15.5041, -7.3957) (15.4731, -7.3736) (15.4419, -7.3518) (15.4105, -7.3303) (15.3789, -7.3094) (15.3467, -7.2895) (15.3204, -7.2745) (15.3003, -7.2641) (15.2868, -7.2574) (15.2799, -7.2542) knots -1 -1 -1 -1 -1 -1 -0.98571429 -0.97142857 -0.95714286 -0.94285714 -0.92857143 -0.91428571 -0.9 -0.88571429 -0.87142857 -0.85714286 -0.84285714 -0.82857143 -0.81428571 -0.8 -0.78571429 -0.77142857 -0.75714286 -0.74285714 -0.72857143 -0.71428571 -0.7 -0.68571429 -0.67142857 -0.65714286 -0.64285714 -0.62857143 -0.61428571 -0.6 -0.58571429 -0.57142857 -0.55714286 -0.54285714 -0.52857143 -0.51428571 -0.5 -0.48571429 -0.47142857 -0.45714286 -0.44285714 -0.42857143 -0.41428571 -0.4 -0.38571429 -0.37142857 -0.35714286 -0.34285714 -0.32857143 -0.31428571 -0.3 -0.28571429 -0.27142857 -0.25714286 -0.24285714 -0.22857143 -0.21428571 -0.2 -0.18571429 -0.17142857 -0.15714286 -0.14285714 -0.12857143 -0.11428571 -0.1 -0.08571429 -0.07142857 -0.05714286 -0.04285714 -0.02857143 -0.01428571 0 0 0 0 0 0
  line L45 (15.2799, -7.2542) -> (15.1377, -7.1866)
  arc A91 (14.8943, -6.5341) -> (15.1377, -7.1866) centre (15.3522, -6.735) ccw
  arc A92 (14.8943, -6.5341) -> (15.1521, -5.9116) centre (0, 0) ccw
  arc A93 (15.7857, -5.6223) -> (15.1521, -5.9116) centre (15.6179, -6.0933) ccw
  line L46 (15.7857, -5.6223) -> (15.934, -5.6751)
  spline S46 degree 5 poles (15.934, -5.6751) (15.9411, -5.6776) (15.9554, -5.6825) (15.9771, -5.6893) (16.0062, -5.6973) (16.043, -5.706) (16.0802, -5.7136) (16.1176, -5.7205) (16.1551, -5.7271) (16.1926, -5.7335) (16.2302, -5.7397) (16.268, -5.7455) (16.3058, -5.7509) (16.3438, -5.7559) (16.3819, -5.7603) (16.4202, -5.7643) (16.4586, -5.7678) (16.497, -5.771) (16.5355, -5.774) (16.5741, -5.7766) (16.6128, -5.779) (16.6515, -5.7811) (16.6904, -5.7829) (16.7293, -5.7844) (16.7682, -5.7856) (16.8073, -5.7864) (16.8464, -5.787) (16.8855, -5.7873) (16.9247, -5.7874) (16.964, -5.7872) (17.0034, -5.7867) (17.0427, -5.786) (17.0822, -5.785) (17.1217, -5.7838) (17.1612, -5.7824) (17.2008, -5.7806) (17.2405, -5.7787) (17.2802, -5.7765) (17.3199, -5.774) (17.3597, -5.7714) (17.3995, -5.7685) (17.4393, -5.7653) (17.4792, -5.762) (17.5192, -5.7584) (17.5591, -5.7546) (17.5991, -5.7506) (17.6392, -5.7463) (17.6793, -5.7418) (17.7194, -5.7372) (17.7595, -5.7323) (17.7997, -5.7272) (17.8399, -5.7218) (17.8801, -5.7163) (17.9204, -5.7106) (17.9607, -5.7046) (18.001, -5.6985) (18.0413, -5.6921) (18.0817, -5.6855) (18.1221, -5.6788) (18.1625, -5.6718) (18.2029, -5.6646) (18.2434, -5.6573) (18.2838, -5.6497) (18.3243, -5.6419) (18.3648, -5.634) (18.4054, -5.6258) (18.4459, -5.6175) (18.4865, -5.609) (18.5271, -5.6002) (18.5677, -5.5913) (18.6083, -5.5822) (18.6408, -5.5748) (18.6652, -5.5691) (18.6814, -5.5653) (18.6895, -5.5634) knots 0 0 0 0 0 0 0.01428571 0.02857143 0.04285714 0.05714286 0.07142857 0.08571429 0.1 0.11428571 0.12857143 0.14285714 0.15714286 0.17142857 0.18571429 0.2 0.21428571 0.22857143 0.24285714 0.25714286 0.27142857 0.28571429 0.3 0.31428571 0.32857143 0.34285714 0.35714286 0.37142857 0.38571429 0.4 0.41428571 0.42857143 0.44285714 0.45714286 0.47142857 0.48571429 0.5 0.51428571 0.52857143 0.54285714 0.55714286 0.57142857 0.58571429 0.6 0.61428571 0.62857143 0.64285714 0.65714286 0.67142857 0.68571429 0.7 0.71428571 0.72857143 0.74285714 0.75714286 0.77142857 0.78571429 0.8 0.81428571 0.82857143 0.84285714 0.85714286 0.87142857 0.88571429 0.9 0.91428571 0.92857143 0.94285714 0.95714286 0.97142857 0.98571429 1 1 1 1 1 1
  arc A94 (18.6895, -5.5634) -> (18.9673, -4.5267) centre (0, 0) ccw
  spline S47 degree 5 poles (18.9673, -4.5267) (18.9612, -4.521) (18.949, -4.5096) (18.9308, -4.4925) (18.9063, -4.4698) (18.8757, -4.4416) (18.845, -4.4136) (18.8142, -4.3857) (18.7834, -4.3581) (18.7524, -4.3306) (18.7214, -4.3032) (18.6903, -4.2761) (18.6591, -4.2491) (18.6278, -4.2223) (18.5965, -4.1957) (18.5651, -4.1693) (18.5336, -4.1431) (18.502, -4.117) (18.4703, -4.0912) (18.4385, -4.0655) (18.4067, -4.04) (18.3748, -4.0147) (18.3428, -3.9896) (18.3107, -3.9647) (18.2786, -3.94) (18.2463, -3.9155) (18.214, -3.8912) (18.1816, -3.867) (18.1491, -3.8431) (18.1166, -3.8194) (18.0839, -3.7959) (18.0512, -3.7727) (18.0184, -3.7496) (17.9856, -3.7267) (17.9526, -3.7041) (17.9196, -3.6817) (17.8865, -3.6595) (17.8533, -3.6375) (17.82, -3.6158) (17.7867, -3.5942) (17.7532, -3.573) (17.7197, -3.5519) (17.6861, -3.5311) (17.6525, -3.5105) (17.6187, -3.4902) (17.5849, -3.4702) (17.551, -3.4504) (17.517, -3.4308) (17.4829, -3.4115) (17.4487, -3.3924) (17.4145, -3.3737) (17.3802, -3.3552) (17.3457, -3.337) (17.3112, -3.3192) (17.2766, -3.3016) (17.2419, -3.2844) (17.2072, -3.2674) (17.1724, -3.2506) (17.1374, -3.2342) (17.1024, -3.2181) (17.0673, -3.2024) (17.0321, -3.1872) (16.9967, -3.1724) (16.9612, -3.1582) (16.9257, -3.1444) (16.89, -3.1309) (16.8543, -3.1177) (16.8185, -3.1047) (16.7827, -3.092) (16.7467, -3.08) (16.7104, -3.0691) (16.6812, -3.0614) (16.6591, -3.0565) (16.6442, -3.0536) (16.6368, -3.0522) knots -1 -1 -1 -1 -1 -1 -0.98571429 -0.97142857 -0.95714286 -0.94285714 -0.92857143 -0.91428571 -0.9 -0.88571429 -0.87142857 -0.85714286 -0.84285714 -0.82857143 -0.81428571 -0.8 -0.78571429 -0.77142857 -0.75714286 -0.74285714 -0.72857143 -0.71428571 -0.7 -0.68571429 -0.67142857 -0.65714286 -0.64285714 -0.62857143 -0.61428571 -0.6 -0.58571429 -0.57142857 -0.55714286 -0.54285714 -0.52857143 -0.51428571 -0.5 -0.48571429 -0.47142857 -0.45714286 -0.44285714 -0.42857143 -0.41428571 -0.4 -0.38571429 -0.37142857 -0.35714286 -0.34285714 -0.32857143 -0.31428571 -0.3 -0.28571429 -0.27142857 -0.25714286 -0.24285714 -0.22857143 -0.21428571 -0.2 -0.18571429 -0.17142857 -0.15714286 -0.14285714 -0.12857143 -0.11428571 -0.1 -0.08571429 -0.07142857 -0.05714286 -0.04285714 -0.02857143 -0.01428571 0 0 0 0 0 0
  line L47 (16.6368, -3.0522) -> (16.482, -3.0238)
  arc A95 (16.0779, -2.4565) -> (16.482, -3.0238) centre (16.5722, -2.532) ccw
  circle A96 centre (0, 0) radius 4.2
  circle A97 centre (0, 0) radius 4.2
  constraint concentric A0 A97
extrude "Extrude1'''" add sketch "Sketch2" along normal mid plane 30 separate body contours A96 A97 makes body 4 in component "Component'"
component "Spur Gear 48 teeth" placed x (0.553628, -0.832764, 0) y (0.832764, 0.553628, 0) z (0, 0, 1) at (54.5011, -0.0327, 0)
component "Spur Gear 24 teeth" placed x (-0.702583, -0.711602, 0) y (0.711602, -0.702583, 0) z (0, 0, 1) at (0, 0, 0)
component "Component" placed x (1, 0, 0) y (0, 1, 0) z (0, 0, 1) at (0, 0, 0)
component "Component'" placed x (1, 0, 0) y (0, 1, 0) z (0, 0, 1) at (0, 0, 0)
